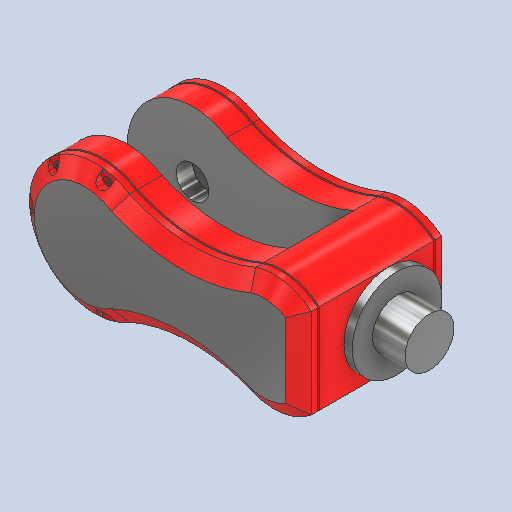
# Autodesk Inventor part: 5
Saved by Autodesk Inventor 2027.1 (Build 311270010, 270A)
## iProperties
Part Number: 5
Material: Allgemein
Document SubType Name: Modellieren
Designer: Asus
Appearance: Chrom - poliert
Author: Asus
Autodesk Inventor part; units mm, degrees
ref_plane "XZ-Ebene" through (0, 0, 0) normal (0, 1, 0) x (-1, 0, 0)
ref_plane "XY-Ebene" through (0, 0, 0) normal (0, 0, 1) x (1, 0, 0)
sketch "Skizze1" plane through (0, 0, 0) normal (0, 0, 1) x (1, 0, 0)
  circle A0 centre (0, 0) radius 27.5
  dimension "d0" = 55
  constraints: 1 centre point, 1 coincident
  measures "d0" diameter of A0
extrude "Extrusion1" add sketch "Skizze1" along normal blind 5
ref_plane "Arbeitsebene1" through (27.5, 0, 0) normal (1, 0, 0) x (0, 1, 0)
sketch "Skizze2" plane through (27.5, 0, 0) normal (1, 0, 0) x (0, 1, 0)
  line L0 (0, 0) -> (0, 5) construction
  line L1 (27.5, 5) -> (-27.5, 5) construction
  line L2 (27.5, 0) -> (-27.5, 0) projected
  line L3 (27.5, 0) -> (-27.5, 0) construction
  line L4 (27.5, 5) -> (-27.5, 5) construction
  arc A0 (34.015, -34.0848) -> (27.5, 0) centre (0, -22.9214) ccw
  arc A1 (-27.5, 0) -> (-34.015, -34.0848) centre (0, -22.9214) ccw
  arc A2 (34.015, -34.0848) -> (34.015, -111.6848) centre (121.9341, -72.8848) ccw
  arc A3 (-34.015, -111.6848) -> (-34.015, -34.0848) centre (-121.9341, -72.8848) ccw
  arc A4 (-34.015, -111.6848) -> (34.015, -111.6848) centre (0, -132.9214) ccw
  point P0 (0, 2.5)
  dimension "d4" = 55
  dimension "d5" = 35.8
  dimension "d6" = 96.1
  dimension "d7" = 40.1
  dimension "d8" = 110
  dimension "d9" = 77.6
  constraints: 10 point on circle, 5 centre point, 4 symmetric about line, 2 vertical alignment, 1 midpoint, 2 other
  measures "d4" distance of L2.start L2.end
  measures "d5" radius of A0
  measures "d6" radius of A2
  measures "d7" radius of A4
  measures "d8" distance of A0.centre A4.centre
  measures "d9" distance of A0.start A2.end
extrude "Extrusion2" add sketch "Skizze2" against normal blind 15
sketch "Skizze3" plane through (27.5, 0, 0) normal (1, 0, 0) x (0, 0, -1)
  line L0 (0, 27.5) -> (0, 0) projected
  line L1 (0, 0) -> (0, -27.5) projected
  arc A0 (0, -27.5) -> (34.0848, -34.015) centre (22.9214, 0) ccw projected
  arc A1 (111.6848, -34.015) -> (34.0848, -34.015) centre (72.8848, -121.9341) ccw projected
  arc A2 (111.6848, -34.015) -> (111.6848, 34.015) centre (132.9214, 0) ccw projected
  arc A3 (34.0848, 34.015) -> (111.6848, 34.015) centre (72.8848, 121.9341) ccw projected
  arc A4 (34.0848, 34.015) -> (0, 27.5) centre (22.9214, 0) ccw projected
  arc A5 (112.861, -31.8016) -> (112.861, 31.8016) centre (132.9214, 0) ccw
  arc A6 (112.861, -31.8016) -> (33.191, -31.6769) centre (72.8848, -121.9341) ccw
  arc A7 (2.5, -26.3032) -> (33.191, -31.6769) centre (22.9214, 0) ccw
  line L2 (2.5, -26.3032) -> (2.5, 0)
  line L3 (2.5, 0) -> (2.5, 26.3032)
  arc A8 (33.191, 31.6769) -> (2.5, 26.3032) centre (22.9214, 0) ccw
  arc A9 (33.191, 31.6769) -> (112.861, 31.8016) centre (72.8848, 121.9341) ccw
  dimension "d12" = 2.5
  constraints: 10 point on circle, 5 centre point, 4 end point, 6 other
  measures "d12" radial gap between concentric circles of A3 A9
extrude "Extrusion3" add sketch "Skizze3" along normal blind 1 contours A6 A7 L2 L3 A8 A9 A5
sketch "Skizze4" plane through (28.5, 0, 0) normal (1, 0, 0) x (0, 0, -1)
  arc A0 (111.6848, -34.015) -> (111.6848, 34.015) centre (132.9214, 0) ccw projected
  arc A1 (34.0848, 34.015) -> (111.6848, 34.015) centre (72.8848, 121.9341) ccw projected
  arc A2 (34.0848, 34.015) -> (0, 27.5) centre (22.9214, 0) ccw projected
  line L0 (0, 27.5) -> (0, 0) projected
  line L1 (0, 0) -> (0, -27.5) projected
  arc A3 (0, -27.5) -> (34.0848, -34.015) centre (22.9214, 0) ccw projected
  arc A4 (111.6848, -34.015) -> (34.0848, -34.015) centre (72.8848, -121.9341) ccw projected
extrude "Extrusion4" add sketch "Skizze4" along normal blind 4
sketch "Skizze5" plane through (32.5, 0, 0) normal (1, 0, 0) x (0, 0, -1)
  line L0 (0, 27.5) -> (0, -27.5) projected
  arc A0 (0, -27.5) -> (34.0848, -34.015) centre (22.9214, 0) ccw projected
  arc A1 (111.6848, -34.015) -> (34.0848, -34.015) centre (72.8848, -121.9341) ccw projected
  arc A2 (111.6848, -34.015) -> (111.6848, 34.015) centre (132.9214, 0) ccw projected
  arc A3 (34.0848, 34.015) -> (111.6848, 34.015) centre (72.8848, 121.9341) ccw projected
  arc A4 (34.0848, 34.015) -> (0, 27.5) centre (22.9214, 0) ccw projected
  point P0 (0, 0)
extrude "Extrusion5" add sketch "Skizze5" along normal blind 6.5 draft -55
sketch "Skizze6" plane through (39, 0, 0) normal (1, 0, 0) x (0, 0, -1)
  line L0 (9.283, -22.7409) -> (9.283, 22.7409) construction
  arc A0 (30.7969, 25.3205) -> (9.283, 22.7409) centre (22.9214, 0) ccw construction
  arc A1 (30.7969, 25.3205) -> (116.0918, 25.8158) centre (72.8848, 121.9341) ccw construction
  arc A2 (116.0918, -25.8158) -> (116.0918, 25.8158) centre (132.9214, 0) ccw construction
  arc A3 (116.0918, -25.8158) -> (30.7969, -25.3205) centre (72.8848, -121.9341) ccw construction
  arc A4 (9.283, -22.7409) -> (30.7969, -25.3205) centre (22.9214, 0) ccw construction
  line L1 (169.7384, 4) -> (174.6384, 4)
  line L2 (174.6384, 4) -> (174.6384, -4)
  line L3 (174.6384, -4) -> (169.7384, -4)
  line L4 (169.7384, -4) -> (169.7384, 4) construction
  line L5 (169.7384, 4) -> (174.6384, -4) construction
  line L6 (174.6384, 4) -> (169.7384, -4) construction
  arc A5 (116.0918, -25.8158) -> (116.0918, 25.8158) centre (132.9214, 0) ccw projected
  arc A6 (169.7384, 4) -> (169.7384, -4) centre (169.7384, 0) ccw
  point P0 (0, 0)
  point P1 (172.1884, 0)
  point P2 (163.7384, 0)
  point P3 (163.7384, 0)
  dimension "d19" = 4.9
  dimension "d20" = 10.9
  dimension "d21" = 4
  dimension "d22" = 8
  constraints: 12 end point, 4 point on circle, 2 midpoint, 2 parallel, 1 centre point, 1 horizontal, 1 horizontal alignment, 1 perpendicular
  measures "d19" distance of L1.start L1.end
  measures "d20" distance from line of L2 point (163.738, 0)
  measures "d21" radius of A6
  measures "d22" distance of L1.end L2.end
extrude "Extrusion6" cut sketch "Skizze6" against normal blind 6.5
sketch "Skizze7" plane through (32.5, 0, 0) normal (1, 0, 0) x (0, 0, -1)
  line L0 (0, -27.5) -> (0, 27.5) construction
  arc A0 (34.0848, 34.015) -> (0, 27.5) centre (22.9214, 0) ccw construction
  arc A1 (34.0848, 34.015) -> (111.6848, 34.015) centre (72.8848, 121.9341) ccw construction
  arc A2 (172.8214, 4) -> (111.6848, 34.015) centre (132.9214, 0) ccw construction
  arc A3 (172.8214, -4) -> (172.8214, 4) centre (132.9214, 0) ccw construction
  arc A4 (111.6848, -34.015) -> (172.8214, -4) centre (132.9214, 0) ccw construction
  arc A5 (111.6848, -34.015) -> (34.0848, -34.015) centre (72.8848, -121.9341) ccw construction
  arc A6 (0, -27.5) -> (34.0848, -34.015) centre (22.9214, 0) ccw construction
  line L1 (172.8214, 4) -> (169.7384, 4) construction
  arc A7 (169.7384, 4) -> (169.7384, -4) centre (169.7384, 0) ccw construction
  line L2 (169.7384, -4) -> (172.8214, -4) construction
  circle A8 centre (168.3214, 0) radius 1.25
  circle A9 centre (168.3214, 0) radius 2.25
  point P0 (0, 0)
  dimension "d25" = 2.5
  dimension "d26" = 1
  dimension "d27" = 35.4
  constraints: 2 centre point, 1 horizontal alignment
  measures "d25" diameter of A8
  measures "d26" radial gap between concentric circles of A8 A9
  measures "d27" distance of A8.centre A3.centre
extrude "Extrusion7" add sketch "Skizze7" along normal blind 0.5
pattern_circular "Runde Anordnung1" count 7 over 360 about axis through (32.5, 0, -132.9214) along (1, 0, 0) of "Extrusion7", "Extrusion6" skipped copies 4 5
sketch "Skizze8" plane through (12.5, 0, 0) normal (-1, 0, 0) x (0, 0, 1)
  arc A0 (0, 27.5) -> (-34.0848, 34.015) centre (-22.9214, 0) ccw projected
  arc A1 (-34.0848, -34.015) -> (0, -27.5) centre (-22.9214, 0) ccw projected
  line L0 (-34.0848, 34.015) -> (-34.0848, -34.015)
  line L1 (0, -27.5) -> (0, 27.5) projected
  line L2 (0, 27.5) -> (0, -27.5)
  point P0 (0, 0)
  point P1 (0, 24.4949)
  point P2 (0, -24.4949)
  constraints: 4 end point, 2 vertical
extrude "Extrusion8" add sketch "Skizze8" along normal blind 40
ref_plane "Arbeitsebene2" through (-7.5, 34.015, -34.0848) normal (-1, 0, 0) x (0, -1, 0)
mirror "Spiegeln1" about plane through (-7.5, 34.015, -34.0848) normal (-1, 0, 0) of "Extrusion2", "Extrusion3", "Extrusion4", "Extrusion5", "Extrusion6", "Extrusion7", "Runde Anordnung1", "Extrusion8"
sketch "Skizze9" plane through (0, 0, 5) normal (0, 0, 1) x (1, 0, 0)
  circle A0 centre (0, 0) radius 15
  dimension "d35" = 30
  constraints: 1 centre point, 1 coincident
  measures "d35" diameter of A0
extrude "Extrusion9" add sketch "Skizze9" along normal blind 20
sketch "Skizze10" plane through (12.5, 0, 0) normal (-1, 0, 0) x (0, 0, 1)
  arc A0 (-111.6848, 34.015) -> (-111.6848, -34.015) centre (-132.9214, 0) ccw projected
  circle A1 centre (-132.9214, 0) radius 10
  point P0 (0, 0)
  dimension "d38" = 20
  constraints: 1 centre point, 1 coincident
  measures "d38" diameter of A1
extrude "Extrusion10" cut sketch "Skizze10" against normal blind 10
mirror "Spiegeln2" about plane through (-7.5, 34.015, -34.0848) normal (-1, 0, 0) of "Extrusion10"
